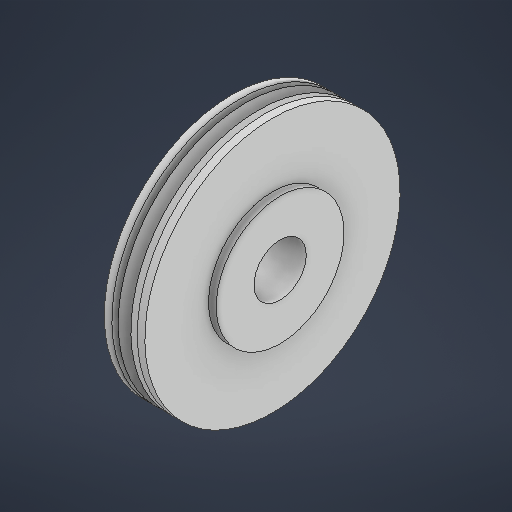
# Autodesk Inventor part: POLEA GIGANTE
Saved by Autodesk Inventor 2027.1 (Build 311270010, 270A)
## iProperties
Created: 2026-11-20
Part Number: POLEA GIGANTE
Material: Generic
Document SubType Name: Modeling
Designer: ASUS
Density: 1 g/cm^3
Appearance: Default
Author: ASUS
Autodesk Inventor part; units mm, degrees
ref_plane "YZ Plane" through (0, 0, 0) normal (1, 0, 0) x (0, 1, 0)
ref_plane "XZ Plane" through (0, 0, 0) normal (0, 1, 0) x (-1, 0, 0)
ref_plane "XY Plane" through (0, 0, 0) normal (0, 0, 1) x (1, 0, 0)
sketch "Sketch1" plane through (0, 0, 0) normal (0, 0, 1) x (1, 0, 0)
  line L0 (46.9401, -0.5888) -> (36.9401, -0.5888)
  line L1 (36.9401, -0.5888) -> (36.9401, 49.7112)
  line L2 (36.9401, 49.7112) -> (46.9401, 49.7112)
  line L3 (46.9401, 49.7112) -> (46.9401, -0.5888)
  line L4 (39.4401, 49.7112) -> (36.9401, 45.7112)
  line L5 (44.4401, 49.7112) -> (46.9401, 46.1503)
  line L6 (39.4401, 49.7112) -> (41.9401, 45.6596)
  line L7 (41.9401, 45.6596) -> (44.4401, 49.7112)
  line L8 (46.9401, -0.5888) -> (46.9401, 24.5612)
  line L9 (46.9401, 24.5612) -> (36.9401, 24.5612)
  line L10 (36.9401, 24.5612) -> (36.9401, 45.7112)
  line L11 (36.9401, 49.7112) -> (33.9401, 49.7112)
  line L12 (36.9401, 49.7112) -> (33.9401, 49.7112)
  line L13 (33.9401, 24.5612) -> (36.9401, 24.5612)
  line L14 (33.9401, 49.7112) -> (33.9401, 24.5612)
  line L15 (46.9401, 49.7112) -> (49.9401, 49.7112)
  line L16 (49.9401, 49.7112) -> (49.9401, 24.5612)
  line L17 (49.9401, 24.5612) -> (46.9401, 24.5612)
  line L18 (49.9401, 24.6112) -> (52.9401, 24.6112)
  line L19 (52.9401, 24.6112) -> (52.9401, 24.5612)
  line L20 (52.9401, 24.5612) -> (49.9401, 24.5612)
  line L21 (46.9401, 9.7112) -> (36.9401, 9.7112)
  line L22 (33.9401, 24.5612) -> (33.9401, 9.7112)
  line L23 (33.9401, 9.7112) -> (36.9401, 9.7112)
  line L24 (46.9401, 9.7112) -> (49.9401, 9.7112)
  line L25 (49.9401, 9.7112) -> (49.9401, 24.5612)
  line L26 (52.9401, 24.5612) -> (52.9401, 9.7112)
  line L27 (52.9401, 9.7112) -> (49.9401, 9.7112)
  point P0 (0, 0)
  point P1 (51.4401, 24.6112)
  dimension "d0" = 10
  dimension "d1" = 50.3
  dimension "d2" = 4
  dimension "d3" = 10.3
  dimension "d4" = 3
  dimension "d5" = 3
  dimension "d6" = 3
  dimension "d7" = 0.05
  dimension "d8" = 5
  dimension "d9" = 2.5
  dimension "d10" = 2.5
  constraints: 56 end point, 11 perpendicular, 11 point on line, 4 equal length, 4 horizontal, 3 midpoint, 1 vertical
  measures "d0" distance of L1.end L2.end
  measures "d1" distance of L0.end L1.end
  measures "d2" distance of L1.end L4.end
  measures "d3" distance between parallel lines of L0 L21
  measures "d4" distance between parallel lines of L1 L14
  measures "d5" distance between parallel lines of L16 L3
  measures "d6" distance between parallel lines of L19 L16
  measures "d7" distance from line of point (51.44, 24.611) L20
  measures "d8" horizontal distance of L6.end L4.end
  measures "d9" distance of L4.start L1.end
  measures "d10" distance of L2.end L5.start
revolve "Revolution1" add sketch "Sketch1" angle 360 about axis through (46.9401, -0.5888, 0) along (-1, 0, 0) contours L21 L1 L9 L3 | L3 L17 L25 L24 | L23 L22 L13 L1 | L9 L1 L4 L6 L7 L5 L3 | L3 L15 L16 L17 | L25 L20 L26 L27 | L13 L14 L11 L1 | L16 L18 L19 L20
body "Solid1"
